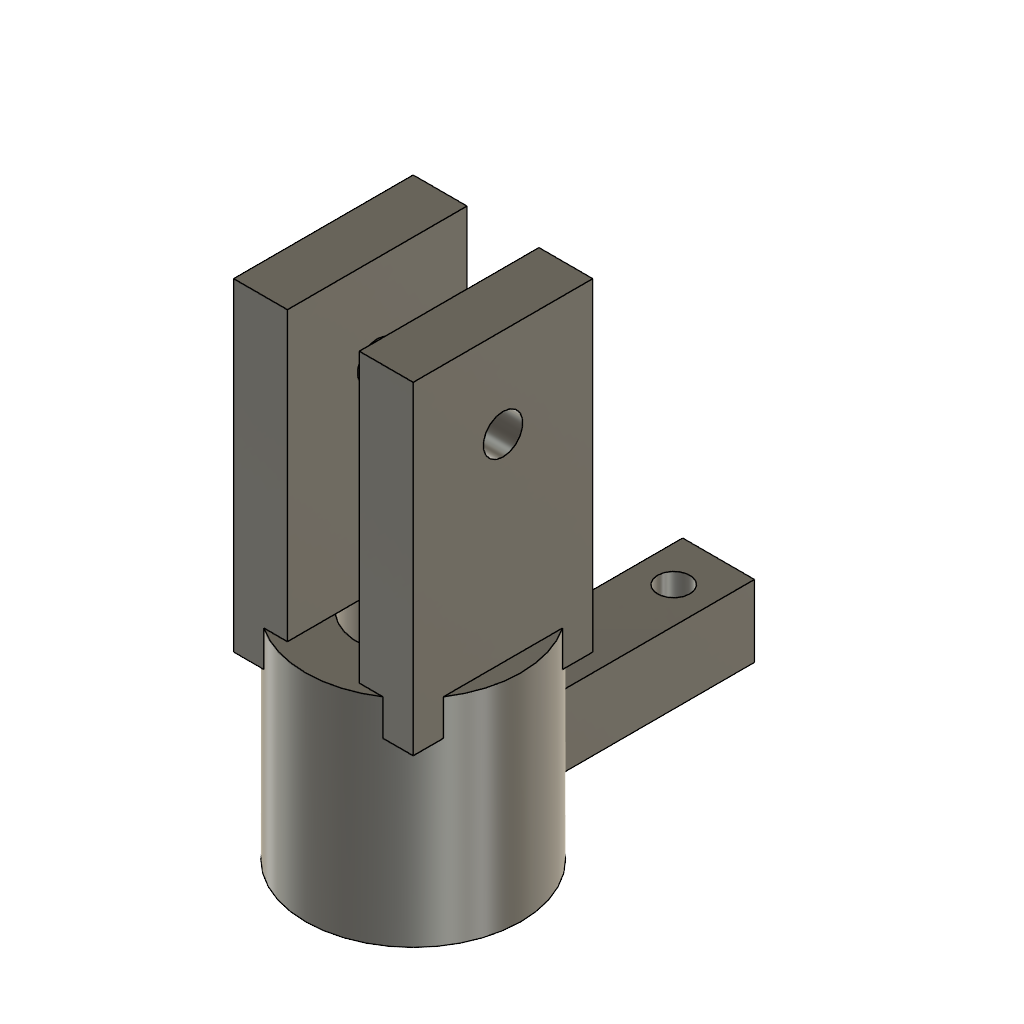
grip-fit-prototype (Autodesk Fusion 360 design; units mm, degrees)
part number: 2026-11-01-14-31-43-601
Autodesk Fusion 360 part; units mm, degrees
ref_plane "WorkPlane1" through (0, 0, 0) normal (0, 0, 1) x (1, 0, 0)
sketch "Bearing housing OD12 assumed" plane through (0, 0, 0) normal (0, 0, 1) x (1, 0, 0)
  circle A0 centre (0, 0) radius 6
extrude "Bearing housing OD12 assumed (1)" add sketch "Bearing housing OD12 assumed" along normal blind 12
ref_plane "WorkPlane2" through (0, 0, 10) normal (0, 0, 1) x (1, 0, 0)
sketch "Cheek A - 3 mm wall assumed" plane through (0, 0, 10) normal (0, 0, 1) x (1, 0, 0)
  line L0 (-5, -5) -> (-2, -5)
  line L1 (-2, -5) -> (-2, 5)
  line L2 (-2, 5) -> (-5, 5)
  line L3 (-5, 5) -> (-5, -5)
extrude "Cheek A - 3 mm wall assumed (1)" add sketch "Cheek A - 3 mm wall assumed" along normal blind 18
ref_plane "WorkPlane3" through (0, 0, 10) normal (0, 0, 1) x (1, 0, 0)
sketch "Cheek B - 3 mm wall assumed" plane through (0, 0, 10) normal (0, 0, 1) x (1, 0, 0)
  line L0 (2, -5) -> (5, -5)
  line L1 (5, -5) -> (5, 5)
  line L2 (5, 5) -> (2, 5)
  line L3 (2, 5) -> (2, -5)
extrude "Cheek B - 3 mm wall assumed (1)" add sketch "Cheek B - 3 mm wall assumed" along normal blind 18
ref_plane "WorkPlane4" through (0, 0, 2) normal (0, 0, 1) x (1, 0, 0)
sketch "Pitch arm - position assumed" plane through (0, 0, 2) normal (0, 0, 1) x (1, 0, 0)
  line L0 (-2, 4) -> (2, 4)
  line L1 (2, 4) -> (2, 17)
  line L2 (2, 17) -> (-2, 17)
  line L3 (-2, 17) -> (-2, 4)
extrude "Pitch arm - position assumed (1)" add sketch "Pitch arm - position assumed" along normal blind 4
ref_plane "WorkPlane5" through (0, 0, 0) normal (0, 0, 1) x (1, 0, 0)
sketch "Internal shoulder relief assumed" plane through (0, 0, 0) normal (0, 0, 1) x (1, 0, 0)
  circle A0 centre (0, 0) radius 2.4
extrude "Internal shoulder relief assumed (1)" cut sketch "Internal shoulder relief assumed" along normal blind 12
ref_plane "WorkPlane6" through (0, 0, 0) normal (0, 0, 1) x (1, 0, 0)
sketch "Inner radial pocket 6.15 assumed allowance" plane through (0, 0, 0) normal (0, 0, 1) x (1, 0, 0)
  circle A0 centre (0, 0) radius 3.075
extrude "Inner radial pocket 6.15 assumed allowance (1)" cut sketch "Inner radial pocket 6.15 assumed allowance" along normal blind 2.5
ref_plane "WorkPlane7" through (0, 0, 3.9) normal (0, 0, 1) x (1, 0, 0)
sketch "Outer radial and thrust access pocket" plane through (0, 0, 3.9) normal (0, 0, 1) x (1, 0, 0)
  circle A0 centre (0, 0) radius 3.075
extrude "Outer radial and thrust access pocket (1)" cut sketch "Outer radial and thrust access pocket" along normal blind 8.1
sketch "Blade bolt 2.2 mm assumed" plane through (0, 0, 0) normal (1, 0, 0) x (0, 0, -1)
  circle A0 centre (-23, 0) radius 1.1
extrude "Extrude8" cut sketch "Blade bolt 2.2 mm assumed" along normal mid plane 40
ref_plane "WorkPlane8" through (0, 0, 2) normal (0, 0, 1) x (1, 0, 0)
sketch "Pitch ball mounting 1.8 mm assumed" plane through (0, 0, 2) normal (0, 0, 1) x (1, 0, 0)
  circle A0 centre (0, 14.5) radius 0.9
extrude "Extrude9" cut sketch "Pitch ball mounting 1.8 mm assumed" along normal blind 4
named bodies: "PETG grip - fit prototype only"
